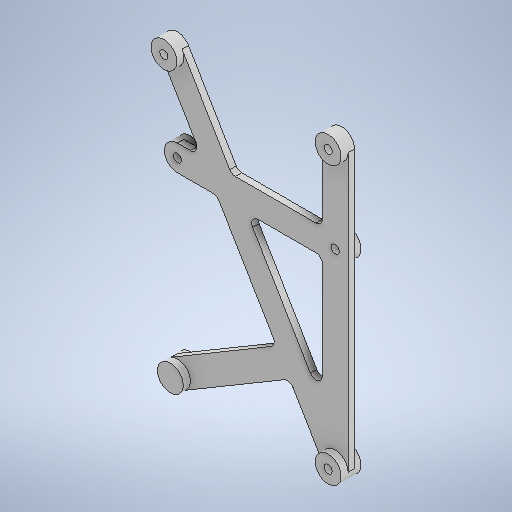
# Autodesk Inventor part: BOARD_SUPPORT
Saved by Autodesk Inventor 2025.3 (Build 293356000, 356)
## iProperties
Created: 2026-09-08
Part Number: BOARD_SUPPORT
Material: 常规
Document SubType Name: Modeling
Designer: shfzf
Density: 1 g/cm^3
Appearance: 默认
Author: shfzf
Autodesk Inventor part; units mm, degrees
ref_plane "YZ Plane" through (0, 0, 0) normal (1, 0, 0) x (0, 1, 0)
ref_plane "XZ Plane" through (0, 0, 0) normal (0, 1, 0) x (-1, 0, 0)
ref_plane "XY Plane" through (0, 0, 0) normal (0, 0, 1) x (1, 0, 0)
sketch "草图1" plane through (0, 0, 0) normal (0, 0, 1) x (1, 0, 0)
  circle A0 centre (25.5, -43) radius 1.25 projected
  circle A1 centre (25.5, 43) radius 1.25 projected
  circle A2 centre (-25.5, -43) radius 1.25 projected
  circle A3 centre (-25.5, 43) radius 1.25 projected
  circle A4 centre (-23.5, 15.0855) radius 1.3645 projected
  circle A5 centre (25.5, 15.0855) radius 1.3645 projected
  circle A6 centre (-23.5, -43) radius 1.3645 projected
  circle A7 centre (25.5, -43) radius 4
  circle A8 centre (25.5, 43) radius 4
  circle A9 centre (25.5, 15.0855) radius 4
  line L0 (29.5, 43) -> (29.5, -43)
  line L1 (21.5, -43) -> (21.5, 43)
  circle A10 centre (-23.5, 15.0855) radius 4
  circle A11 centre (-25.5, 43) radius 4
  line L2 (22.0595, -45.0403) -> (-28.9405, 40.9597)
  line L3 (-22.0595, 45.0403) -> (28.9405, -40.9597)
  line L4 (-23.5, 19.0855) -> (25.5, 19.0855)
  line L5 (25.5, 11.0855) -> (-23.5, 11.0855)
  circle A12 centre (-23.5, 15.0855) radius 1.25
  circle A13 centre (25.5, 15.0855) radius 1.25
  circle A14 centre (-23.5, -43) radius 4
  line L6 (-25.5403, -39.5595) -> (7.2705, -20.1019)
  line L7 (-21.4597, -46.4405) -> (11.3511, -26.983)
  point P0 (0, 0)
  point P1 (21.5, -28.4129)
  point P2 (-1.9235, 11.0855)
  point P3 (21.5, 11.0855)
  point P4 (21.5, 19.0855)
  point P5 (-6.6677, 19.0855)
  point P6 (-15.9686, 19.0855)
  point P7 (-11.2244, 11.0855)
  dimension "d0" = 8
  dimension "d1" = 8
  dimension "d2" = 8
  dimension "d3" = 8
  dimension "d4" = 8
  dimension "d5" = 2.5
  dimension "d6" = 2.5
  dimension "d20" = 8
  constraints: 16 end point, 14 point on circle, 13 tangent, 8 centre point, 8 coincident, 2 point on line, 1 parallel, 1 perpendicular, 1 vertical
  measures "d0" diameter of A7
  measures "d1" diameter of A8
  measures "d2" diameter of A9
  measures "d3" diameter of A10
  measures "d4" diameter of A11
  measures "d5" diameter of A12
  measures "d6" diameter of A13
  measures "d20" diameter of A14
extrude "拉伸1" add sketch "草图1" along normal blind 2 contours A2 A6 | A2 A6 | A6 A2 | A4 | A5 | A7 | A7 L3 L1 L5 A9 L0 | A7 L1 L3 | L2 L5 L3 L1 A7 | A9 | A9 L4 L1 A8 L0 | L7 A14 L6 L2 | A9 L1 L4 | L5 L1 A9 | A8 | L5 L3 L4 L1 | L5 L2 L4 L3 | A14 | L4 L2 A11 L3 | L5 A10 L4 L2 | A11 | A10
fillet "圆角1" radius 2 7 edges at (21.5, 11.0855, 1) (-1.9235, 11.0855, 1) (21.5, -28.4129, 1) (21.5, 19.0855, 1) (-6.6677, 19.0855, 1) (-11.2244, 11.0855, 1) (-15.9686, 19.0855, 1)
sketch "草图2" plane through (0, 0, 0) normal (0, 0, -1) x (-1, 0, 0)
  arc A0 (-21.5, 43) -> (-29.5, 43) centre (-25.5, 43) ccw projected
  line L0 (-29.5, -43) -> (-29.5, 43) projected
  arc A1 (-29.5, -43) -> (-22.0595, -45.0403) centre (-25.5, -43) ccw projected
  line L1 (-11.3511, -26.983) -> (-22.0595, -45.0403) projected
  arc A2 (12.3636, 11.0855) -> (10.6434, 10.1057) centre (12.3636, 9.0855) ccw projected
  line L2 (23.5, 11.0855) -> (12.3636, 11.0855) projected
  arc A3 (23.5, 11.0855) -> (23.5, 19.0855) centre (23.5, 15.0855) ccw projected
  line L3 (19.4799, 19.0855) -> (23.5, 19.0855) projected
  arc A4 (17.7596, 22.1057) -> (19.4799, 19.0855) centre (19.4799, 21.0855) ccw projected
  line L4 (28.9405, 40.9597) -> (17.7596, 22.1057) projected
  arc A5 (28.9405, 40.9597) -> (22.0595, 45.0403) centre (25.5, 43) ccw projected
  line L5 (7.2488, 20.0654) -> (22.0595, 45.0403) projected
  arc A6 (5.5285, 19.0855) -> (7.2488, 20.0654) centre (5.5285, 21.0855) ccw projected
  line L6 (-19.5, 19.0855) -> (5.5285, 19.0855) projected
  arc A7 (-21.5, 21.0855) -> (-19.5, 19.0855) centre (-19.5, 21.0855) ccw projected
  line L7 (-21.5, 43) -> (-21.5, 21.0855) projected
  circle A8 centre (-25.5, 43) radius 1.25 projected
  circle A9 centre (25.5, 43) radius 1.25 projected
  arc A10 (-21.5, -21.1194) -> (-17.7797, -22.1396) centre (-19.5, -21.1194) ccw projected
  line L8 (-21.5, 9.0855) -> (-21.5, -21.1194) projected
  arc A11 (-19.5, 11.0855) -> (-21.5, 9.0855) centre (-19.5, 9.0855) ccw projected
  line L9 (-1.5878, 11.0855) -> (-19.5, 11.0855) projected
  arc A12 (0.1325, 8.0654) -> (-1.5878, 11.0855) centre (-1.5878, 9.0855) ccw projected
  line L10 (-17.7797, -22.1396) -> (0.1325, 8.0654) projected
  circle A13 centre (-25.5, -43) radius 1.25 projected
  circle A14 centre (-25.5, 15.0855) radius 4
  circle A15 centre (23.5, 15.0855) radius 4
  circle A16 centre (-25.5, -43) radius 4
  line L11 (21.4597, -46.4405) -> (-11.3511, -26.983) projected
  arc A17 (21.4597, -46.4405) -> (25.5403, -39.5595) centre (23.5, -43) ccw projected
  line L12 (-7.2705, -20.1019) -> (25.5403, -39.5595) projected
  line L13 (10.6434, 10.1057) -> (-7.2705, -20.1019) projected
  circle A18 centre (23.5, 15.0855) radius 1.25 projected
  circle A19 centre (-25.5, 15.0855) radius 1.25 projected
  circle A20 centre (-25.5, -43) radius 1.25 projected
  point P0 (0, 0)
  point P1 (-22.0595, -45.0403)
  point P2 (23.5, 19.0855)
  dimension "d10" = 8
  dimension "d11" = 8
  dimension "d12" = 8
  constraints: 3 centre point, 1 coincident
  measures "d10" diameter of A14
  measures "d11" diameter of A15
  measures "d12" diameter of A16
extrude "拉伸2" add sketch "草图2" along normal blind 2 contours A14 | A16 A1 | A3 A15
sketch "草图3" plane through (0, 0, 2) normal (0, 0, 1) x (1, 0, 0)
  arc A0 (29.5, 43) -> (21.5, 43) centre (25.5, 43) ccw projected
  line L0 (21.5, 43) -> (21.5, 21.0855) projected
  arc A1 (19.5, 19.0855) -> (21.5, 21.0855) centre (19.5, 21.0855) ccw projected
  line L1 (19.5, 19.0855) -> (-5.5285, 19.0855) projected
  arc A2 (-7.2488, 20.0654) -> (-5.5285, 19.0855) centre (-5.5285, 21.0855) ccw projected
  line L2 (-7.2488, 20.0654) -> (-22.0595, 45.0403) projected
  arc A3 (-22.0595, 45.0403) -> (-28.9405, 40.9597) centre (-25.5, 43) ccw projected
  line L3 (-28.9405, 40.9597) -> (-17.7596, 22.1057) projected
  arc A4 (-19.4799, 19.0855) -> (-17.7596, 22.1057) centre (-19.4799, 21.0855) ccw projected
  line L4 (-19.4799, 19.0855) -> (-23.5, 19.0855) projected
  arc A5 (-23.5, 19.0855) -> (-23.5, 11.0855) centre (-23.5, 15.0855) ccw projected
  line L5 (-23.5, 11.0855) -> (-12.3636, 11.0855) projected
  arc A6 (-10.6434, 10.1057) -> (-12.3636, 11.0855) centre (-12.3636, 9.0855) ccw projected
  line L6 (-10.6434, 10.1057) -> (7.2705, -20.1019) projected
  arc A7 (22.0595, -45.0403) -> (29.5, -43) centre (25.5, -43) ccw projected
  line L7 (29.5, -43) -> (29.5, 43) projected
  circle A8 centre (25.5, 43) radius 1.25 projected
  circle A9 centre (-25.5, 43) radius 1.25 projected
  line L8 (17.7797, -22.1396) -> (-0.1325, 8.0654) projected
  arc A10 (1.5878, 11.0855) -> (-0.1325, 8.0654) centre (1.5878, 9.0855) ccw projected
  line L9 (1.5878, 11.0855) -> (19.5, 11.0855) projected
  arc A11 (21.5, 9.0855) -> (19.5, 11.0855) centre (19.5, 9.0855) ccw projected
  line L10 (21.5, 9.0855) -> (21.5, -21.1194) projected
  arc A12 (17.7797, -22.1396) -> (21.5, -21.1194) centre (19.5, -21.1194) ccw projected
  circle A13 centre (25.5, -43) radius 1.25 projected
  circle A14 centre (-25.5, 43) radius 4
  circle A15 centre (25.5, 43) radius 4
  circle A16 centre (25.5, -43) radius 4
  line L11 (7.2705, -20.1019) -> (-25.5403, -39.5595) projected
  arc A17 (-25.5403, -39.5595) -> (-21.4597, -46.4405) centre (-23.5, -43) ccw projected
  line L12 (-21.4597, -46.4405) -> (11.3511, -26.983) projected
  line L13 (11.3511, -26.983) -> (22.0595, -45.0403) projected
  point P0 (0, 0)
  point P1 (29.5, -43)
  point P2 (-28.9405, 40.9597)
  point P3 (21.5, 43)
  dimension "d15" = 8
  dimension "d16" = 8
  dimension "d17" = 8
  constraints: 3 centre point, 3 coincident
  measures "d15" diameter of A14
  measures "d16" diameter of A15
  measures "d17" diameter of A16
extrude "拉伸3" add sketch "草图3" along normal blind 2.2 contours A15 A0 | A7 A16 | A14 A3
fillet "圆角2" radius 2 2 edges at (11.3511, -26.983, 1) (7.2705, -20.1019, 1)
sketch "草图4" plane through (25.5, -43, -2) normal (0, 0, -1) x (-1, 0, 0)
  arc A0 (46.9597, -3.4405) -> (51.0403, 3.4405) centre (49, 0) ccw projected
  circle A1 centre (49, 0) radius 4
  point P0 (25.5, 43)
  point P1 (51.0403, 3.4405)
  point P2 (46.9597, -3.4405)
  constraints: 1 centre point, 1 coincident, 1 concentric
extrude "拉伸4" add sketch "草图4" against normal up to surface (6.2 mm away)
sketch "草图6" plane through (-23.5, -43, -2) normal (0, 0, -1) x (-1, 0, 0)
  circle A0 centre (0, 0) radius 4 projected
  circle A1 centre (0, 0) radius 1.25
  point P0 (-23.5, 43)
  dimension "d27" = 2.5
  constraints: 1 centre point, 1 coincident
  measures "d27" diameter of A1
extrude "拉伸6" cut sketch "草图6" against normal blind 4 contours A1
